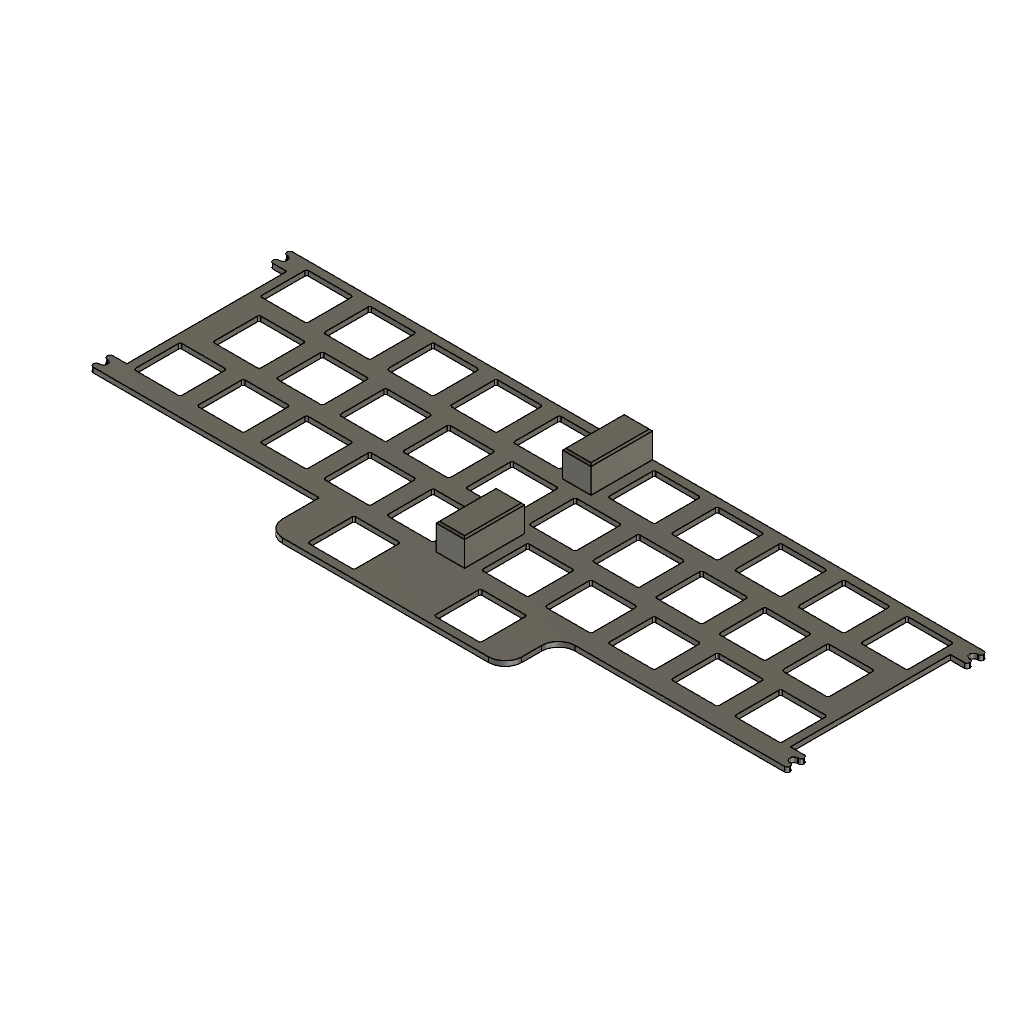
Hullstone Plate w blockers (Autodesk Fusion 360 design; units mm, degrees)
Autodesk Fusion 360 part; units mm, degrees
sketch "treadstone32platelayout" plane through (0, 0, 0) normal (0, 0, 1) x (1, 0, 0)
  line L0 (3.025, -2.525) -> (16.025, -2.525)
  line L1 (3.025, -16.525) -> (16.025, -16.525)
  line L2 (2.525, -3.025) -> (2.525, -16.025)
  line L3 (16.525, -3.025) -> (16.525, -16.025)
  arc A0 (3.025, -2.525) -> (2.525, -3.025) centre (3.025, -3.025) ccw
  arc A1 (16.525, -3.025) -> (16.025, -2.525) centre (16.025, -3.025) ccw
  arc A2 (2.525, -16.025) -> (3.025, -16.525) centre (3.025, -16.025) ccw
  arc A3 (16.025, -16.525) -> (16.525, -16.025) centre (16.025, -16.025) ccw
  line L4 (22.075, -2.525) -> (35.075, -2.525)
  line L5 (22.075, -16.525) -> (35.075, -16.525)
  line L6 (21.575, -3.025) -> (21.575, -16.025)
  line L7 (35.575, -3.025) -> (35.575, -16.025)
  arc A4 (22.075, -2.525) -> (21.575, -3.025) centre (22.075, -3.025) ccw
  arc A5 (35.575, -3.025) -> (35.075, -2.525) centre (35.075, -3.025) ccw
  arc A6 (21.575, -16.025) -> (22.075, -16.525) centre (22.075, -16.025) ccw
  arc A7 (35.075, -16.525) -> (35.575, -16.025) centre (35.075, -16.025) ccw
  line L8 (41.125, -2.525) -> (54.125, -2.525)
  line L9 (41.125, -16.525) -> (54.125, -16.525)
  line L10 (40.625, -3.025) -> (40.625, -16.025)
  line L11 (54.625, -3.025) -> (54.625, -16.025)
  arc A8 (41.125, -2.525) -> (40.625, -3.025) centre (41.125, -3.025) ccw
  arc A9 (54.625, -3.025) -> (54.125, -2.525) centre (54.125, -3.025) ccw
  arc A10 (40.625, -16.025) -> (41.125, -16.525) centre (41.125, -16.025) ccw
  arc A11 (54.125, -16.525) -> (54.625, -16.025) centre (54.125, -16.025) ccw
  line L12 (60.175, -2.525) -> (73.175, -2.525)
  line L13 (60.175, -16.525) -> (73.175, -16.525)
  line L14 (59.675, -3.025) -> (59.675, -16.025)
  line L15 (73.675, -3.025) -> (73.675, -16.025)
  arc A12 (60.175, -2.525) -> (59.675, -3.025) centre (60.175, -3.025) ccw
  arc A13 (73.675, -3.025) -> (73.175, -2.525) centre (73.175, -3.025) ccw
  arc A14 (59.675, -16.025) -> (60.175, -16.525) centre (60.175, -16.025) ccw
  arc A15 (73.175, -16.525) -> (73.675, -16.025) centre (73.175, -16.025) ccw
  line L16 (79.225, -2.525) -> (92.225, -2.525)
  line L17 (79.225, -16.525) -> (92.225, -16.525)
  line L18 (78.725, -3.025) -> (78.725, -16.025)
  line L19 (92.725, -3.025) -> (92.725, -16.025)
  arc A16 (79.225, -2.525) -> (78.725, -3.025) centre (79.225, -3.025) ccw
  arc A17 (92.725, -3.025) -> (92.225, -2.525) centre (92.225, -3.025) ccw
  arc A18 (78.725, -16.025) -> (79.225, -16.525) centre (79.225, -16.025) ccw
  arc A19 (92.225, -16.525) -> (92.725, -16.025) centre (92.225, -16.025) ccw
  line L20 (107.8, -2.525) -> (120.8, -2.525)
  line L21 (107.8, -16.525) -> (120.8, -16.525)
  line L22 (107.3, -3.025) -> (107.3, -16.025)
  line L23 (121.3, -3.025) -> (121.3, -16.025)
  arc A20 (107.8, -2.525) -> (107.3, -3.025) centre (107.8, -3.025) ccw
  arc A21 (121.3, -3.025) -> (120.8, -2.525) centre (120.8, -3.025) ccw
  arc A22 (107.3, -16.025) -> (107.8, -16.525) centre (107.8, -16.025) ccw
  arc A23 (120.8, -16.525) -> (121.3, -16.025) centre (120.8, -16.025) ccw
  line L24 (126.85, -2.525) -> (139.85, -2.525)
  line L25 (126.85, -16.525) -> (139.85, -16.525)
  line L26 (126.35, -3.025) -> (126.35, -16.025)
  line L27 (140.35, -3.025) -> (140.35, -16.025)
  arc A24 (126.85, -2.525) -> (126.35, -3.025) centre (126.85, -3.025) ccw
  arc A25 (140.35, -3.025) -> (139.85, -2.525) centre (139.85, -3.025) ccw
  arc A26 (126.35, -16.025) -> (126.85, -16.525) centre (126.85, -16.025) ccw
  arc A27 (139.85, -16.525) -> (140.35, -16.025) centre (139.85, -16.025) ccw
  line L28 (145.9, -2.525) -> (158.9, -2.525)
  line L29 (145.9, -16.525) -> (158.9, -16.525)
  line L30 (145.4, -3.025) -> (145.4, -16.025)
  line L31 (159.4, -3.025) -> (159.4, -16.025)
  arc A28 (145.9, -2.525) -> (145.4, -3.025) centre (145.9, -3.025) ccw
  arc A29 (159.4, -3.025) -> (158.9, -2.525) centre (158.9, -3.025) ccw
  arc A30 (145.4, -16.025) -> (145.9, -16.525) centre (145.9, -16.025) ccw
  arc A31 (158.9, -16.525) -> (159.4, -16.025) centre (158.9, -16.025) ccw
  line L32 (164.95, -2.525) -> (177.95, -2.525)
  line L33 (164.95, -16.525) -> (177.95, -16.525)
  line L34 (164.45, -3.025) -> (164.45, -16.025)
  line L35 (178.45, -3.025) -> (178.45, -16.025)
  arc A32 (164.95, -2.525) -> (164.45, -3.025) centre (164.95, -3.025) ccw
  arc A33 (178.45, -3.025) -> (177.95, -2.525) centre (177.95, -3.025) ccw
  arc A34 (164.45, -16.025) -> (164.95, -16.525) centre (164.95, -16.025) ccw
  arc A35 (177.95, -16.525) -> (178.45, -16.025) centre (177.95, -16.025) ccw
  line L36 (184, -2.525) -> (197, -2.525)
  line L37 (184, -16.525) -> (197, -16.525)
  line L38 (183.5, -3.025) -> (183.5, -16.025)
  line L39 (197.5, -3.025) -> (197.5, -16.025)
  arc A36 (184, -2.525) -> (183.5, -3.025) centre (184, -3.025) ccw
  arc A37 (197.5, -3.025) -> (197, -2.525) centre (197, -3.025) ccw
  arc A38 (183.5, -16.025) -> (184, -16.525) centre (184, -16.025) ccw
  arc A39 (197, -16.525) -> (197.5, -16.025) centre (197, -16.025) ccw
  line L40 (7.7875, -21.575) -> (20.7875, -21.575)
  line L41 (7.7875, -35.575) -> (20.7875, -35.575)
  line L42 (7.2875, -22.075) -> (7.2875, -35.075)
  line L43 (21.2875, -22.075) -> (21.2875, -35.075)
  arc A40 (7.7875, -21.575) -> (7.2875, -22.075) centre (7.7875, -22.075) ccw
  arc A41 (21.2875, -22.075) -> (20.7875, -21.575) centre (20.7875, -22.075) ccw
  arc A42 (7.2875, -35.075) -> (7.7875, -35.575) centre (7.7875, -35.075) ccw
  arc A43 (20.7875, -35.575) -> (21.2875, -35.075) centre (20.7875, -35.075) ccw
  line L44 (26.8375, -21.575) -> (39.8375, -21.575)
  line L45 (26.8375, -35.575) -> (39.8375, -35.575)
  line L46 (26.3375, -22.075) -> (26.3375, -35.075)
  line L47 (40.3375, -22.075) -> (40.3375, -35.075)
  arc A44 (26.8375, -21.575) -> (26.3375, -22.075) centre (26.8375, -22.075) ccw
  arc A45 (40.3375, -22.075) -> (39.8375, -21.575) centre (39.8375, -22.075) ccw
  arc A46 (26.3375, -35.075) -> (26.8375, -35.575) centre (26.8375, -35.075) ccw
  arc A47 (39.8375, -35.575) -> (40.3375, -35.075) centre (39.8375, -35.075) ccw
  line L48 (45.8875, -21.575) -> (58.8875, -21.575)
  line L49 (45.8875, -35.575) -> (58.8875, -35.575)
  line L50 (45.3875, -22.075) -> (45.3875, -35.075)
  line L51 (59.3875, -22.075) -> (59.3875, -35.075)
  arc A48 (45.8875, -21.575) -> (45.3875, -22.075) centre (45.8875, -22.075) ccw
  arc A49 (59.3875, -22.075) -> (58.8875, -21.575) centre (58.8875, -22.075) ccw
  arc A50 (45.3875, -35.075) -> (45.8875, -35.575) centre (45.8875, -35.075) ccw
  arc A51 (58.8875, -35.575) -> (59.3875, -35.075) centre (58.8875, -35.075) ccw
  line L52 (64.9375, -21.575) -> (77.9375, -21.575)
  line L53 (64.9375, -35.575) -> (77.9375, -35.575)
  line L54 (64.4375, -22.075) -> (64.4375, -35.075)
  line L55 (78.4375, -22.075) -> (78.4375, -35.075)
  arc A52 (64.9375, -21.575) -> (64.4375, -22.075) centre (64.9375, -22.075) ccw
  arc A53 (78.4375, -22.075) -> (77.9375, -21.575) centre (77.9375, -22.075) ccw
  arc A54 (64.4375, -35.075) -> (64.9375, -35.575) centre (64.9375, -35.075) ccw
  arc A55 (77.9375, -35.575) -> (78.4375, -35.075) centre (77.9375, -35.075) ccw
  line L56 (83.9875, -21.575) -> (96.9875, -21.575)
  line L57 (83.9875, -35.575) -> (96.9875, -35.575)
  line L58 (83.4875, -22.075) -> (83.4875, -35.075)
  line L59 (97.4875, -22.075) -> (97.4875, -35.075)
  arc A56 (83.9875, -21.575) -> (83.4875, -22.075) centre (83.9875, -22.075) ccw
  arc A57 (97.4875, -22.075) -> (96.9875, -21.575) centre (96.9875, -22.075) ccw
  arc A58 (83.4875, -35.075) -> (83.9875, -35.575) centre (83.9875, -35.075) ccw
  arc A59 (96.9875, -35.575) -> (97.4875, -35.075) centre (96.9875, -35.075) ccw
  line L60 (103.0375, -21.575) -> (116.0375, -21.575)
  line L61 (103.0375, -35.575) -> (116.0375, -35.575)
  line L62 (102.5375, -22.075) -> (102.5375, -35.075)
  line L63 (116.5375, -22.075) -> (116.5375, -35.075)
  arc A60 (103.0375, -21.575) -> (102.5375, -22.075) centre (103.0375, -22.075) ccw
  arc A61 (116.5375, -22.075) -> (116.0375, -21.575) centre (116.0375, -22.075) ccw
  arc A62 (102.5375, -35.075) -> (103.0375, -35.575) centre (103.0375, -35.075) ccw
  arc A63 (116.0375, -35.575) -> (116.5375, -35.075) centre (116.0375, -35.075) ccw
  line L64 (122.0875, -21.575) -> (135.0875, -21.575)
  line L65 (122.0875, -35.575) -> (135.0875, -35.575)
  line L66 (121.5875, -22.075) -> (121.5875, -35.075)
  line L67 (135.5875, -22.075) -> (135.5875, -35.075)
  arc A64 (122.0875, -21.575) -> (121.5875, -22.075) centre (122.0875, -22.075) ccw
  arc A65 (135.5875, -22.075) -> (135.0875, -21.575) centre (135.0875, -22.075) ccw
  arc A66 (121.5875, -35.075) -> (122.0875, -35.575) centre (122.0875, -35.075) ccw
  arc A67 (135.0875, -35.575) -> (135.5875, -35.075) centre (135.0875, -35.075) ccw
  line L68 (141.1375, -21.575) -> (154.1375, -21.575)
  line L69 (141.1375, -35.575) -> (154.1375, -35.575)
  line L70 (140.6375, -22.075) -> (140.6375, -35.075)
  line L71 (154.6375, -22.075) -> (154.6375, -35.075)
  arc A68 (141.1375, -21.575) -> (140.6375, -22.075) centre (141.1375, -22.075) ccw
  arc A69 (154.6375, -22.075) -> (154.1375, -21.575) centre (154.1375, -22.075) ccw
  arc A70 (140.6375, -35.075) -> (141.1375, -35.575) centre (141.1375, -35.075) ccw
  arc A71 (154.1375, -35.575) -> (154.6375, -35.075) centre (154.1375, -35.075) ccw
  line L72 (160.1875, -21.575) -> (173.1875, -21.575)
  line L73 (160.1875, -35.575) -> (173.1875, -35.575)
  line L74 (159.6875, -22.075) -> (159.6875, -35.075)
  line L75 (173.6875, -22.075) -> (173.6875, -35.075)
  arc A72 (160.1875, -21.575) -> (159.6875, -22.075) centre (160.1875, -22.075) ccw
  arc A73 (173.6875, -22.075) -> (173.1875, -21.575) centre (173.1875, -22.075) ccw
  arc A74 (159.6875, -35.075) -> (160.1875, -35.575) centre (160.1875, -35.075) ccw
  arc A75 (173.1875, -35.575) -> (173.6875, -35.075) centre (173.1875, -35.075) ccw
  line L76 (179.2375, -21.575) -> (192.2375, -21.575)
  line L77 (179.2375, -35.575) -> (192.2375, -35.575)
  line L78 (178.7375, -22.075) -> (178.7375, -35.075)
  line L79 (192.7375, -22.075) -> (192.7375, -35.075)
  arc A76 (179.2375, -21.575) -> (178.7375, -22.075) centre (179.2375, -22.075) ccw
  arc A77 (192.7375, -22.075) -> (192.2375, -21.575) centre (192.2375, -22.075) ccw
  arc A78 (178.7375, -35.075) -> (179.2375, -35.575) centre (179.2375, -35.075) ccw
  arc A79 (192.2375, -35.575) -> (192.7375, -35.075) centre (192.2375, -35.075) ccw
  line L80 (3.025, -40.625) -> (16.025, -40.625)
  line L81 (3.025, -54.625) -> (16.025, -54.625)
  line L82 (2.525, -41.125) -> (2.525, -54.125)
  line L83 (16.525, -41.125) -> (16.525, -54.125)
  arc A80 (3.025, -40.625) -> (2.525, -41.125) centre (3.025, -41.125) ccw
  arc A81 (16.525, -41.125) -> (16.025, -40.625) centre (16.025, -41.125) ccw
  arc A82 (2.525, -54.125) -> (3.025, -54.625) centre (3.025, -54.125) ccw
  arc A83 (16.025, -54.625) -> (16.525, -54.125) centre (16.025, -54.125) ccw
  line L84 (22.075, -40.625) -> (35.075, -40.625)
  line L85 (22.075, -54.625) -> (35.075, -54.625)
  line L86 (21.575, -41.125) -> (21.575, -54.125)
  line L87 (35.575, -41.125) -> (35.575, -54.125)
  arc A84 (22.075, -40.625) -> (21.575, -41.125) centre (22.075, -41.125) ccw
  arc A85 (35.575, -41.125) -> (35.075, -40.625) centre (35.075, -41.125) ccw
  arc A86 (21.575, -54.125) -> (22.075, -54.625) centre (22.075, -54.125) ccw
  arc A87 (35.075, -54.625) -> (35.575, -54.125) centre (35.075, -54.125) ccw
  line L88 (41.125, -40.625) -> (54.125, -40.625)
  line L89 (41.125, -54.625) -> (54.125, -54.625)
  line L90 (40.625, -41.125) -> (40.625, -54.125)
  line L91 (54.625, -41.125) -> (54.625, -54.125)
  arc A88 (41.125, -40.625) -> (40.625, -41.125) centre (41.125, -41.125) ccw
  arc A89 (54.625, -41.125) -> (54.125, -40.625) centre (54.125, -41.125) ccw
  arc A90 (40.625, -54.125) -> (41.125, -54.625) centre (41.125, -54.125) ccw
  arc A91 (54.125, -54.625) -> (54.625, -54.125) centre (54.125, -54.125) ccw
  line L92 (60.175, -40.625) -> (73.175, -40.625)
  line L93 (60.175, -54.625) -> (73.175, -54.625)
  line L94 (59.675, -41.125) -> (59.675, -54.125)
  line L95 (73.675, -41.125) -> (73.675, -54.125)
  arc A92 (60.175, -40.625) -> (59.675, -41.125) centre (60.175, -41.125) ccw
  arc A93 (73.675, -41.125) -> (73.175, -40.625) centre (73.175, -41.125) ccw
  arc A94 (59.675, -54.125) -> (60.175, -54.625) centre (60.175, -54.125) ccw
  arc A95 (73.175, -54.625) -> (73.675, -54.125) centre (73.175, -54.125) ccw
  line L96 (79.225, -40.625) -> (92.225, -40.625)
  line L97 (79.225, -54.625) -> (92.225, -54.625)
  line L98 (78.725, -41.125) -> (78.725, -54.125)
  line L99 (92.725, -41.125) -> (92.725, -54.125)
  arc A96 (79.225, -40.625) -> (78.725, -41.125) centre (79.225, -41.125) ccw
  arc A97 (92.725, -41.125) -> (92.225, -40.625) centre (92.225, -41.125) ccw
  arc A98 (78.725, -54.125) -> (79.225, -54.625) centre (79.225, -54.125) ccw
  arc A99 (92.225, -54.625) -> (92.725, -54.125) centre (92.225, -54.125) ccw
  line L100 (107.8, -40.625) -> (120.8, -40.625)
  line L101 (107.8, -54.625) -> (120.8, -54.625)
  line L102 (107.3, -41.125) -> (107.3, -54.125)
  line L103 (121.3, -41.125) -> (121.3, -54.125)
  arc A100 (107.8, -40.625) -> (107.3, -41.125) centre (107.8, -41.125) ccw
  arc A101 (121.3, -41.125) -> (120.8, -40.625) centre (120.8, -41.125) ccw
  arc A102 (107.3, -54.125) -> (107.8, -54.625) centre (107.8, -54.125) ccw
  arc A103 (120.8, -54.625) -> (121.3, -54.125) centre (120.8, -54.125) ccw
  line L104 (126.85, -40.625) -> (139.85, -40.625)
  line L105 (126.85, -54.625) -> (139.85, -54.625)
  line L106 (126.35, -41.125) -> (126.35, -54.125)
  line L107 (140.35, -41.125) -> (140.35, -54.125)
  arc A104 (126.85, -40.625) -> (126.35, -41.125) centre (126.85, -41.125) ccw
  arc A105 (140.35, -41.125) -> (139.85, -40.625) centre (139.85, -41.125) ccw
  arc A106 (126.35, -54.125) -> (126.85, -54.625) centre (126.85, -54.125) ccw
  arc A107 (139.85, -54.625) -> (140.35, -54.125) centre (139.85, -54.125) ccw
  line L108 (145.9, -40.625) -> (158.9, -40.625)
  line L109 (145.9, -54.625) -> (158.9, -54.625)
  line L110 (145.4, -41.125) -> (145.4, -54.125)
  line L111 (159.4, -41.125) -> (159.4, -54.125)
  arc A108 (145.9, -40.625) -> (145.4, -41.125) centre (145.9, -41.125) ccw
  arc A109 (159.4, -41.125) -> (158.9, -40.625) centre (158.9, -41.125) ccw
  arc A110 (145.4, -54.125) -> (145.9, -54.625) centre (145.9, -54.125) ccw
  arc A111 (158.9, -54.625) -> (159.4, -54.125) centre (158.9, -54.125) ccw
  line L112 (164.95, -40.625) -> (177.95, -40.625)
  line L113 (164.95, -54.625) -> (177.95, -54.625)
  line L114 (164.45, -41.125) -> (164.45, -54.125)
  line L115 (178.45, -41.125) -> (178.45, -54.125)
  arc A112 (164.95, -40.625) -> (164.45, -41.125) centre (164.95, -41.125) ccw
  arc A113 (178.45, -41.125) -> (177.95, -40.625) centre (177.95, -41.125) ccw
  arc A114 (164.45, -54.125) -> (164.95, -54.625) centre (164.95, -54.125) ccw
  arc A115 (177.95, -54.625) -> (178.45, -54.125) centre (177.95, -54.125) ccw
  line L116 (184, -40.625) -> (197, -40.625)
  line L117 (184, -54.625) -> (197, -54.625)
  line L118 (183.5, -41.125) -> (183.5, -54.125)
  line L119 (197.5, -41.125) -> (197.5, -54.125)
  arc A116 (184, -40.625) -> (183.5, -41.125) centre (184, -41.125) ccw
  arc A117 (197.5, -41.125) -> (197, -40.625) centre (197, -41.125) ccw
  arc A118 (183.5, -54.125) -> (184, -54.625) centre (184, -54.125) ccw
  arc A119 (197, -54.625) -> (197.5, -54.125) centre (197, -54.125) ccw
  line L120 (74.4625, -59.675) -> (87.4625, -59.675)
  line L121 (74.4625, -73.675) -> (87.4625, -73.675)
  line L122 (73.9625, -60.1812) -> (73.9625, -73.175)
  line L123 (87.9625, -60.175) -> (87.9625, -73.175)
  arc A120 (74.4625, -59.675) -> (73.9625, -60.1812) centre (74.4625, -60.175) ccw
  arc A121 (87.9625, -60.175) -> (87.4625, -59.675) centre (87.4625, -60.175) ccw
  arc A122 (73.9625, -73.175) -> (74.4625, -73.675) centre (74.4625, -73.175) ccw
  arc A123 (87.4625, -73.675) -> (87.9625, -73.175) centre (87.4625, -73.175) ccw
  line L124 (112.5625, -59.675) -> (125.5625, -59.675)
  line L125 (112.5625, -73.675) -> (125.5625, -73.675)
  line L126 (112.0625, -60.175) -> (112.0625, -73.175)
  line L127 (126.0625, -60.1812) -> (126.0625, -73.175)
  arc A124 (112.5625, -59.675) -> (112.0625, -60.175) centre (112.5625, -60.175) ccw
  arc A125 (126.0625, -60.1812) -> (125.5625, -59.675) centre (125.5625, -60.175) ccw
  arc A126 (112.0625, -73.175) -> (112.5625, -73.675) centre (112.5625, -73.175) ccw
  arc A127 (125.5625, -73.675) -> (126.0625, -73.175) centre (125.5625, -73.175) ccw
  line L128 (68.9625, -76.2) -> (131.0625, -76.2)
  line L129 (0, 0) -> (200.025, 0)
  line L130 (0, -60.1812) -> (0, 0)
  line L131 (200.025, -60.1812) -> (200.025, 0)
  line L132 (136.0625, -65.1812) -> (136.0625, -71.2)
  line L133 (63.9625, -60.1812) -> (63.9625, -71.2)
  line L134 (200.025, -60.1812) -> (141.0625, -60.1812)
  line L135 (63.9625, -60.1812) -> (0, -60.1812)
  arc A128 (63.9625, -71.2) -> (68.9625, -76.2) centre (68.9625, -71.2) ccw
  arc A129 (131.0625, -76.2) -> (136.0625, -71.2) centre (131.0625, -71.2) ccw
  arc A130 (141.0625, -60.1812) -> (136.0625, -65.1812) centre (141.0625, -65.1812) ccw
  line L136 (200.025, -60.1812) -> (204.225, -60.1812)
  line L137 (204.225, -54.1812) -> (200.025, -54.1812)
  line L138 (200.025, -54.1812) -> (200.025, -60.1812)
  line L139 (200.025, 0) -> (204.225, 0)
  line L140 (204.225, -6) -> (200.025, -6)
  line L141 (200.025, -6) -> (200.025, 0)
  line L142 (0, 0) -> (-4.2, 0)
  line L143 (-4.2, -6) -> (0, -6)
  line L144 (0, -6) -> (0, 0)
  line L145 (0, -60.1812) -> (-4.2, -60.1812)
  line L146 (-4.2, -54.1812) -> (0, -54.1812)
  line L147 (0, -54.1812) -> (0, -60.1812)
  line L148 (-4.0098, -55.9812) -> (-4.2, -55.9812)
  line L149 (-4.0075, -58.3812) -> (-4.2, -58.3812)
  arc A131 (-4.012, -58.3812) -> (-4.0098, -55.9812) centre (-4.0098, -57.1812) ccw
  line L150 (-5, -59.3812) -> (-5, -59.1812)
  line L151 (-5, -55.1812) -> (-5, -54.9812)
  line L152 (204.025, -55.975) -> (204.225, -55.975)
  line L153 (204.025, -58.375) -> (204.225, -58.375)
  arc A132 (204.025, -55.975) -> (204.025, -58.375) centre (204.025, -57.175) ccw
  line L154 (205.025, -59.3812) -> (205.025, -59.175)
  line L155 (205.025, -55.175) -> (205.025, -54.9812)
  line L156 (205.025, -0.8) -> (205.025, -1)
  line L157 (205.025, -5) -> (205.025, -5.2)
  arc A133 (204.025, -1.8) -> (204.0255, -4.2) centre (204.025, -3) ccw
  line L158 (204.0245, -4.2) -> (204.225, -4.2)
  line L159 (204.025, -1.8) -> (204.225, -1.8)
  line L160 (-4, -1.8) -> (-4.2, -1.8)
  line L161 (-3.9994, -4.2) -> (-4.2, -4.2)
  line L162 (-5, -0.8) -> (-5, -1)
  line L163 (-5, -5) -> (-5, -5.2)
  arc A134 (-4.0006, -4.2) -> (-4, -1.8) centre (-4, -3) ccw
  arc A135 (-5, -1) -> (-4.2, -1.8) centre (-4.2, -1) ccw
  arc A136 (-4.2, 0) -> (-5, -0.8) centre (-4.2, -0.8) ccw
  arc A137 (-4.2, -4.2) -> (-5, -5) centre (-4.2, -5) ccw
  arc A138 (-5, -5.2) -> (-4.2, -6) centre (-4.2, -5.2) ccw
  arc A139 (-4.2, -54.1812) -> (-5, -54.9812) centre (-4.2, -54.9812) ccw
  arc A140 (-5, -55.1812) -> (-4.2, -55.9812) centre (-4.2, -55.1812) ccw
  arc A141 (-4.2, -58.3812) -> (-5, -59.1812) centre (-4.2, -59.1812) ccw
  arc A142 (-5, -59.3812) -> (-4.2, -60.1812) centre (-4.2, -59.3812) ccw
  arc A143 (205.025, -59.175) -> (204.225, -58.375) centre (204.225, -59.175) ccw
  arc A144 (204.225, -60.1812) -> (205.025, -59.3812) centre (204.225, -59.3812) ccw
  arc A145 (204.225, -55.975) -> (205.025, -55.175) centre (204.225, -55.175) ccw
  arc A146 (205.025, -54.9812) -> (204.225, -54.1812) centre (204.225, -54.9812) ccw
  arc A147 (204.225, -6) -> (205.025, -5.2) centre (204.225, -5.2) ccw
  arc A148 (205.025, -5) -> (204.225, -4.2) centre (204.225, -5) ccw
  arc A149 (204.225, -1.8) -> (205.025, -1) centre (204.225, -1) ccw
  arc A150 (205.025, -0.8) -> (204.225, 0) centre (204.225, -0.8) ccw
  point P0 (136.0625, -60.1812)
  point P1 (205.025, -60.1812)
  point P2 (205.025, 0)
  point P3 (-5, 0)
  dimension "d1" = 10
  dimension "d2" = 10
  dimension "d3" = 5
  dimension "d4" = 5
  dimension "d5" = 6
  dimension "d8" = 5
  dimension "d9" = 6
  dimension "d10" = 2.4
  dimension "d11" = 2.4
  dimension "d13" = 2.4
  dimension "d15" = 2.4
  dimension "d16" = 0.8
  dimension "d19" = 3
  constraint perpendicular L130 L134
  constraint perpendicular L128 L132
  constraint perpendicular L128 L133
  constraint collinear L134 L135
  constraint tangent L133 A128
  constraint tangent L128 A128
  constraint tangent L128 A129
  constraint tangent L132 A129
  constraint equal A128 A129
  constraint coincident P0 L134
  constraint coincident P0 L132
  constraint tangent L134 A130
  constraint tangent L132 A130
  constraint equal A128 A130
  constraint horizontal L136
  constraint vertical L154
  constraint horizontal L137
  constraint vertical L138
  constraint horizontal L139
  constraint vertical L156
  constraint horizontal L140
  constraint vertical L141
  constraint horizontal L142
  constraint vertical L162
  constraint horizontal L143
  constraint vertical L144
  constraint horizontal L145
  constraint vertical L150
  constraint horizontal L146
  constraint vertical L147
  constraint perpendicular L148 L150
  constraint perpendicular L149 L150
  constraint coincident L149 A131.start
  constraint collinear L150 L151
  constraint coincident A131 L149.start
  constraint tangent L152 A132
  constraint tangent L153 A132
  constraint collinear L154 L155
  constraint collinear L156 L157
  constraint coincident A133 L158.start
  constraint coincident L158 A133.end
  constraint horizontal L160
  constraint collinear L162 L163
  constraint coincident L161 A134.start
  constraint coincident A134 L161.start
  constraint tangent L160 A135
  constraint tangent L162 A135
  constraint coincident P3 L162
  constraint coincident P3 L142
  constraint tangent L162 A136
  constraint tangent L142 A136
  constraint equal A135 A136
  constraint tangent L161 A137
  constraint tangent L163 A137
  constraint equal A135 A137
  constraint tangent L163 A138
  constraint tangent L143 A138
  constraint equal A135 A138
  constraint tangent L146 A139
  constraint tangent L151 A139
  constraint equal A135 A139
  constraint tangent L151 A140
  constraint tangent L148 A140
  constraint equal A135 A140
  constraint tangent L149 A141
  constraint tangent L150 A141
  constraint equal A135 A141
  constraint tangent L150 A142
  constraint tangent L145 A142
  constraint equal A135 A142
  constraint tangent L153 A143
  constraint tangent L154 A143
  constraint equal A135 A143
  constraint coincident P1 L154
  constraint coincident P1 L136
  constraint tangent L154 A144
  constraint tangent L136 A144
  constraint equal A135 A144
  constraint tangent L152 A145
  constraint tangent L155 A145
  constraint equal A135 A145
  constraint tangent L155 A146
  constraint tangent L137 A146
  constraint equal A135 A146
  constraint tangent L140 A147
  constraint tangent L157 A147
  constraint equal A135 A147
  constraint tangent L157 A148
  constraint tangent L158 A148
  constraint equal A135 A148
  constraint tangent L159 A149
  constraint tangent L156 A149
  constraint equal A135 A149
  constraint coincident P2 L139
  constraint coincident P2 L156
  constraint tangent L139 A150
  constraint tangent L156 A150
  constraint equal A135 A150
  measures "d1" distance of L127.start P0
  measures "d2" distance of L122.start L133.start
  measures "d3" radius of A128
  measures "d4" distance of L131.start P1
  measures "d5" distance of L131.start L137.end
  measures "d8" distance of L129.start P3
  measures "d9" distance of L130.start L146.end
  measures "d10" diameter of A131
  measures "d11" diameter of A134
  measures "d13" diameter of A133
  measures "d15" diameter of A132
  measures "d16" radius of A135
  measures "d19" distance of L146 A131.centre
extrude "Extrude1" add sketch "treadstone32platelayout" along normal blind 1.5
sketch "Sketch2" plane through (0, 0, 1.5) normal (0, 0, 1) x (-1, 0, 0)
  arc A0 (-164.95, 40.625) -> (-164.45, 41.125) centre (-164.95, 41.125) ccw
  line L0 (-164.95, 40.625) -> (-177.95, 40.625)
  arc A1 (-178.45, 41.125) -> (-177.95, 40.625) centre (-177.95, 41.125) ccw
  line L1 (-178.45, 41.125) -> (-178.45, 54.125)
  arc A2 (-177.95, 54.625) -> (-178.45, 54.125) centre (-177.95, 54.125) ccw
  line L2 (-177.95, 54.625) -> (-164.95, 54.625)
  arc A3 (-164.45, 54.125) -> (-164.95, 54.625) centre (-164.95, 54.125) ccw
  line L3 (-164.45, 54.125) -> (-164.45, 41.125)
  arc A4 (-184, 40.625) -> (-183.5, 41.125) centre (-184, 41.125) ccw
  line L4 (-184, 40.625) -> (-197, 40.625)
  arc A5 (-197.5, 41.125) -> (-197, 40.625) centre (-197, 41.125) ccw
  line L5 (-197.5, 41.125) -> (-197.5, 54.125)
  arc A6 (-197, 54.625) -> (-197.5, 54.125) centre (-197, 54.125) ccw
  line L6 (-197, 54.625) -> (-184, 54.625)
  arc A7 (-183.5, 54.125) -> (-184, 54.625) centre (-184, 54.125) ccw
  line L7 (-183.5, 54.125) -> (-183.5, 41.125)
  arc A8 (-74.4625, 59.675) -> (-73.9625, 60.1812) centre (-74.4625, 60.175) ccw
  line L8 (-74.4625, 59.675) -> (-87.4625, 59.675)
  arc A9 (-87.9625, 60.175) -> (-87.4625, 59.675) centre (-87.4625, 60.175) ccw
  line L9 (-87.9625, 60.175) -> (-87.9625, 73.175)
  arc A10 (-87.4625, 73.675) -> (-87.9625, 73.175) centre (-87.4625, 73.175) ccw
  line L10 (-87.4625, 73.675) -> (-74.4625, 73.675)
  arc A11 (-73.9625, 73.175) -> (-74.4625, 73.675) centre (-74.4625, 73.175) ccw
  line L11 (-73.9625, 73.175) -> (-73.9625, 60.1812)
  arc A12 (-145.9, 40.625) -> (-145.4, 41.125) centre (-145.9, 41.125) ccw
  line L12 (-145.9, 40.625) -> (-158.9, 40.625)
  arc A13 (-159.4, 41.125) -> (-158.9, 40.625) centre (-158.9, 41.125) ccw
  line L13 (-159.4, 41.125) -> (-159.4, 54.125)
  arc A14 (-158.9, 54.625) -> (-159.4, 54.125) centre (-158.9, 54.125) ccw
  line L14 (-158.9, 54.625) -> (-145.9, 54.625)
  arc A15 (-145.4, 54.125) -> (-145.9, 54.625) centre (-145.9, 54.125) ccw
  line L15 (-145.4, 54.125) -> (-145.4, 41.125)
  arc A16 (-26.8375, 21.575) -> (-26.3375, 22.075) centre (-26.8375, 22.075) ccw
  line L16 (-26.8375, 21.575) -> (-39.8375, 21.575)
  arc A17 (-40.3375, 22.075) -> (-39.8375, 21.575) centre (-39.8375, 22.075) ccw
  line L17 (-40.3375, 22.075) -> (-40.3375, 35.075)
  arc A18 (-39.8375, 35.575) -> (-40.3375, 35.075) centre (-39.8375, 35.075) ccw
  line L18 (-39.8375, 35.575) -> (-26.8375, 35.575)
  arc A19 (-26.3375, 35.075) -> (-26.8375, 35.575) centre (-26.8375, 35.075) ccw
  line L19 (-26.3375, 35.075) -> (-26.3375, 22.075)
  arc A20 (-45.8875, 21.575) -> (-45.3875, 22.075) centre (-45.8875, 22.075) ccw
  line L20 (-45.8875, 21.575) -> (-58.8875, 21.575)
  arc A21 (-59.3875, 22.075) -> (-58.8875, 21.575) centre (-58.8875, 22.075) ccw
  line L21 (-59.3875, 22.075) -> (-59.3875, 35.075)
  arc A22 (-58.8875, 35.575) -> (-59.3875, 35.075) centre (-58.8875, 35.075) ccw
  line L22 (-58.8875, 35.575) -> (-45.8875, 35.575)
  arc A23 (-45.3875, 35.075) -> (-45.8875, 35.575) centre (-45.8875, 35.075) ccw
  line L23 (-45.3875, 35.075) -> (-45.3875, 22.075)
  arc A24 (-126.85, 40.625) -> (-126.35, 41.125) centre (-126.85, 41.125) ccw
  line L24 (-126.85, 40.625) -> (-139.85, 40.625)
  arc A25 (-140.35, 41.125) -> (-139.85, 40.625) centre (-139.85, 41.125) ccw
  line L25 (-140.35, 41.125) -> (-140.35, 54.125)
  arc A26 (-139.85, 54.625) -> (-140.35, 54.125) centre (-139.85, 54.125) ccw
  line L26 (-139.85, 54.625) -> (-126.85, 54.625)
  arc A27 (-126.35, 54.125) -> (-126.85, 54.625) centre (-126.85, 54.125) ccw
  line L27 (-126.35, 54.125) -> (-126.35, 41.125)
  arc A28 (-107.8, 40.625) -> (-107.3, 41.125) centre (-107.8, 41.125) ccw
  line L28 (-107.8, 40.625) -> (-120.8, 40.625)
  arc A29 (-121.3, 41.125) -> (-120.8, 40.625) centre (-120.8, 41.125) ccw
  line L29 (-121.3, 41.125) -> (-121.3, 54.125)
  arc A30 (-120.8, 54.625) -> (-121.3, 54.125) centre (-120.8, 54.125) ccw
  line L30 (-120.8, 54.625) -> (-107.8, 54.625)
  arc A31 (-107.3, 54.125) -> (-107.8, 54.625) centre (-107.8, 54.125) ccw
  line L31 (-107.3, 54.125) -> (-107.3, 41.125)
  arc A32 (-112.5625, 59.675) -> (-112.0625, 60.175) centre (-112.5625, 60.175) ccw
  line L32 (-112.5625, 59.675) -> (-125.5625, 59.675)
  arc A33 (-126.0625, 60.1812) -> (-125.5625, 59.675) centre (-125.5625, 60.175) ccw
  line L33 (-126.0625, 60.1812) -> (-126.0625, 73.175)
  arc A34 (-125.5625, 73.675) -> (-126.0625, 73.175) centre (-125.5625, 73.175) ccw
  line L34 (-125.5625, 73.675) -> (-112.5625, 73.675)
  arc A35 (-112.0625, 73.175) -> (-112.5625, 73.675) centre (-112.5625, 73.175) ccw
  line L35 (-112.0625, 73.175) -> (-112.0625, 60.175)
  arc A36 (-79.225, 40.625) -> (-78.725, 41.125) centre (-79.225, 41.125) ccw
  line L36 (-79.225, 40.625) -> (-92.225, 40.625)
  arc A37 (-92.725, 41.125) -> (-92.225, 40.625) centre (-92.225, 41.125) ccw
  line L37 (-92.725, 41.125) -> (-92.725, 54.125)
  arc A38 (-92.225, 54.625) -> (-92.725, 54.125) centre (-92.225, 54.125) ccw
  line L38 (-92.225, 54.625) -> (-79.225, 54.625)
  arc A39 (-78.725, 54.125) -> (-79.225, 54.625) centre (-79.225, 54.125) ccw
  line L39 (-78.725, 54.125) -> (-78.725, 41.125)
  arc A40 (-60.175, 40.625) -> (-59.675, 41.125) centre (-60.175, 41.125) ccw
  line L40 (-60.175, 40.625) -> (-73.175, 40.625)
  arc A41 (-73.675, 41.125) -> (-73.175, 40.625) centre (-73.175, 41.125) ccw
  line L41 (-73.675, 41.125) -> (-73.675, 54.125)
  arc A42 (-73.175, 54.625) -> (-73.675, 54.125) centre (-73.175, 54.125) ccw
  line L42 (-73.175, 54.625) -> (-60.175, 54.625)
  arc A43 (-59.675, 54.125) -> (-60.175, 54.625) centre (-60.175, 54.125) ccw
  line L43 (-59.675, 54.125) -> (-59.675, 41.125)
  arc A44 (-41.125, 40.625) -> (-40.625, 41.125) centre (-41.125, 41.125) ccw
  line L44 (-41.125, 40.625) -> (-54.125, 40.625)
  arc A45 (-54.625, 41.125) -> (-54.125, 40.625) centre (-54.125, 41.125) ccw
  line L45 (-54.625, 41.125) -> (-54.625, 54.125)
  arc A46 (-54.125, 54.625) -> (-54.625, 54.125) centre (-54.125, 54.125) ccw
  line L46 (-54.125, 54.625) -> (-41.125, 54.625)
  arc A47 (-40.625, 54.125) -> (-41.125, 54.625) centre (-41.125, 54.125) ccw
  line L47 (-40.625, 54.125) -> (-40.625, 41.125)
  arc A48 (-22.075, 40.625) -> (-21.575, 41.125) centre (-22.075, 41.125) ccw
  line L48 (-22.075, 40.625) -> (-35.075, 40.625)
  arc A49 (-35.575, 41.125) -> (-35.075, 40.625) centre (-35.075, 41.125) ccw
  line L49 (-35.575, 41.125) -> (-35.575, 54.125)
  arc A50 (-35.075, 54.625) -> (-35.575, 54.125) centre (-35.075, 54.125) ccw
  line L50 (-35.075, 54.625) -> (-22.075, 54.625)
  arc A51 (-21.575, 54.125) -> (-22.075, 54.625) centre (-22.075, 54.125) ccw
  line L51 (-21.575, 54.125) -> (-21.575, 41.125)
  arc A52 (-3.025, 40.625) -> (-2.525, 41.125) centre (-3.025, 41.125) ccw
  line L52 (-3.025, 40.625) -> (-16.025, 40.625)
  arc A53 (-16.525, 41.125) -> (-16.025, 40.625) centre (-16.025, 41.125) ccw
  line L53 (-16.525, 41.125) -> (-16.525, 54.125)
  arc A54 (-16.025, 54.625) -> (-16.525, 54.125) centre (-16.025, 54.125) ccw
  line L54 (-16.025, 54.625) -> (-3.025, 54.625)
  arc A55 (-2.525, 54.125) -> (-3.025, 54.625) centre (-3.025, 54.125) ccw
  line L55 (-2.525, 54.125) -> (-2.525, 41.125)
  arc A56 (-179.2375, 21.575) -> (-178.7375, 22.075) centre (-179.2375, 22.075) ccw
  line L56 (-179.2375, 21.575) -> (-192.2375, 21.575)
  arc A57 (-192.7375, 22.075) -> (-192.2375, 21.575) centre (-192.2375, 22.075) ccw
  line L57 (-192.7375, 22.075) -> (-192.7375, 35.075)
  arc A58 (-192.2375, 35.575) -> (-192.7375, 35.075) centre (-192.2375, 35.075) ccw
  line L58 (-192.2375, 35.575) -> (-179.2375, 35.575)
  arc A59 (-178.7375, 35.075) -> (-179.2375, 35.575) centre (-179.2375, 35.075) ccw
  line L59 (-178.7375, 35.075) -> (-178.7375, 22.075)
  arc A60 (-160.1875, 21.575) -> (-159.6875, 22.075) centre (-160.1875, 22.075) ccw
  line L60 (-160.1875, 21.575) -> (-173.1875, 21.575)
  arc A61 (-173.6875, 22.075) -> (-173.1875, 21.575) centre (-173.1875, 22.075) ccw
  line L61 (-173.6875, 22.075) -> (-173.6875, 35.075)
  arc A62 (-173.1875, 35.575) -> (-173.6875, 35.075) centre (-173.1875, 35.075) ccw
  line L62 (-173.1875, 35.575) -> (-160.1875, 35.575)
  arc A63 (-159.6875, 35.075) -> (-160.1875, 35.575) centre (-160.1875, 35.075) ccw
  line L63 (-159.6875, 35.075) -> (-159.6875, 22.075)
  arc A64 (-141.1375, 21.575) -> (-140.6375, 22.075) centre (-141.1375, 22.075) ccw
  line L64 (-141.1375, 21.575) -> (-154.1375, 21.575)
  arc A65 (-154.6375, 22.075) -> (-154.1375, 21.575) centre (-154.1375, 22.075) ccw
  line L65 (-154.6375, 22.075) -> (-154.6375, 35.075)
  arc A66 (-154.1375, 35.575) -> (-154.6375, 35.075) centre (-154.1375, 35.075) ccw
  line L66 (-154.1375, 35.575) -> (-141.1375, 35.575)
  arc A67 (-140.6375, 35.075) -> (-141.1375, 35.575) centre (-141.1375, 35.075) ccw
  line L67 (-140.6375, 35.075) -> (-140.6375, 22.075)
  arc A68 (-122.0875, 21.575) -> (-121.5875, 22.075) centre (-122.0875, 22.075) ccw
  line L68 (-122.0875, 21.575) -> (-135.0875, 21.575)
  arc A69 (-135.5875, 22.075) -> (-135.0875, 21.575) centre (-135.0875, 22.075) ccw
  line L69 (-135.5875, 22.075) -> (-135.5875, 35.075)
  arc A70 (-135.0875, 35.575) -> (-135.5875, 35.075) centre (-135.0875, 35.075) ccw
  line L70 (-135.0875, 35.575) -> (-122.0875, 35.575)
  arc A71 (-121.5875, 35.075) -> (-122.0875, 35.575) centre (-122.0875, 35.075) ccw
  line L71 (-121.5875, 35.075) -> (-121.5875, 22.075)
  arc A72 (-103.0375, 21.575) -> (-102.5375, 22.075) centre (-103.0375, 22.075) ccw
  line L72 (-103.0375, 21.575) -> (-116.0375, 21.575)
  arc A73 (-116.5375, 22.075) -> (-116.0375, 21.575) centre (-116.0375, 22.075) ccw
  line L73 (-116.5375, 22.075) -> (-116.5375, 35.075)
  arc A74 (-116.0375, 35.575) -> (-116.5375, 35.075) centre (-116.0375, 35.075) ccw
  line L74 (-116.0375, 35.575) -> (-103.0375, 35.575)
  arc A75 (-102.5375, 35.075) -> (-103.0375, 35.575) centre (-103.0375, 35.075) ccw
  line L75 (-102.5375, 35.075) -> (-102.5375, 22.075)
  arc A76 (-83.9875, 21.575) -> (-83.4875, 22.075) centre (-83.9875, 22.075) ccw
  line L76 (-83.9875, 21.575) -> (-96.9875, 21.575)
  arc A77 (-97.4875, 22.075) -> (-96.9875, 21.575) centre (-96.9875, 22.075) ccw
  line L77 (-97.4875, 22.075) -> (-97.4875, 35.075)
  arc A78 (-96.9875, 35.575) -> (-97.4875, 35.075) centre (-96.9875, 35.075) ccw
  line L78 (-96.9875, 35.575) -> (-83.9875, 35.575)
  arc A79 (-83.4875, 35.075) -> (-83.9875, 35.575) centre (-83.9875, 35.075) ccw
  line L79 (-83.4875, 35.075) -> (-83.4875, 22.075)
  arc A80 (-64.9375, 21.575) -> (-64.4375, 22.075) centre (-64.9375, 22.075) ccw
  line L80 (-64.9375, 21.575) -> (-77.9375, 21.575)
  arc A81 (-78.4375, 22.075) -> (-77.9375, 21.575) centre (-77.9375, 22.075) ccw
  line L81 (-78.4375, 22.075) -> (-78.4375, 35.075)
  arc A82 (-77.9375, 35.575) -> (-78.4375, 35.075) centre (-77.9375, 35.075) ccw
  line L82 (-77.9375, 35.575) -> (-64.9375, 35.575)
  arc A83 (-64.4375, 35.075) -> (-64.9375, 35.575) centre (-64.9375, 35.075) ccw
  line L83 (-64.4375, 35.075) -> (-64.4375, 22.075)
  arc A84 (-145.9, 2.525) -> (-145.4, 3.025) centre (-145.9, 3.025) ccw
  line L84 (-145.9, 2.525) -> (-158.9, 2.525)
  arc A85 (-159.4, 3.025) -> (-158.9, 2.525) centre (-158.9, 3.025) ccw
  line L85 (-159.4, 3.025) -> (-159.4, 16.025)
  arc A86 (-158.9, 16.525) -> (-159.4, 16.025) centre (-158.9, 16.025) ccw
  line L86 (-158.9, 16.525) -> (-145.9, 16.525)
  arc A87 (-145.4, 16.025) -> (-145.9, 16.525) centre (-145.9, 16.025) ccw
  line L87 (-145.4, 16.025) -> (-145.4, 3.025)
  arc A88 (-164.95, 2.525) -> (-164.45, 3.025) centre (-164.95, 3.025) ccw
  line L88 (-164.95, 2.525) -> (-177.95, 2.525)
  arc A89 (-178.45, 3.025) -> (-177.95, 2.525) centre (-177.95, 3.025) ccw
  line L89 (-178.45, 3.025) -> (-178.45, 16.025)
  arc A90 (-177.95, 16.525) -> (-178.45, 16.025) centre (-177.95, 16.025) ccw
  line L90 (-177.95, 16.525) -> (-164.95, 16.525)
  arc A91 (-164.45, 16.025) -> (-164.95, 16.525) centre (-164.95, 16.025) ccw
  line L91 (-164.45, 16.025) -> (-164.45, 3.025)
  arc A92 (-184, 2.525) -> (-183.5, 3.025) centre (-184, 3.025) ccw
  line L92 (-184, 2.525) -> (-197, 2.525)
  arc A93 (-197.5, 3.025) -> (-197, 2.525) centre (-197, 3.025) ccw
  line L93 (-197.5, 3.025) -> (-197.5, 16.025)
  arc A94 (-197, 16.525) -> (-197.5, 16.025) centre (-197, 16.025) ccw
  line L94 (-197, 16.525) -> (-184, 16.525)
  arc A95 (-183.5, 16.025) -> (-184, 16.525) centre (-184, 16.025) ccw
  line L95 (-183.5, 16.025) -> (-183.5, 3.025)
  arc A96 (-7.7875, 21.575) -> (-7.2875, 22.075) centre (-7.7875, 22.075) ccw
  line L96 (-7.7875, 21.575) -> (-20.7875, 21.575)
  arc A97 (-21.2875, 22.075) -> (-20.7875, 21.575) centre (-20.7875, 22.075) ccw
  line L97 (-21.2875, 22.075) -> (-21.2875, 35.075)
  arc A98 (-20.7875, 35.575) -> (-21.2875, 35.075) centre (-20.7875, 35.075) ccw
  line L98 (-20.7875, 35.575) -> (-7.7875, 35.575)
  arc A99 (-7.2875, 35.075) -> (-7.7875, 35.575) centre (-7.7875, 35.075) ccw
  line L99 (-7.2875, 35.075) -> (-7.2875, 22.075)
  arc A100 (-107.8, 2.525) -> (-107.3, 3.025) centre (-107.8, 3.025) ccw
  line L100 (-107.8, 2.525) -> (-120.8, 2.525)
  arc A101 (-121.3, 3.025) -> (-120.8, 2.525) centre (-120.8, 3.025) ccw
  line L101 (-121.3, 3.025) -> (-121.3, 16.025)
  arc A102 (-120.8, 16.525) -> (-121.3, 16.025) centre (-120.8, 16.025) ccw
  line L102 (-120.8, 16.525) -> (-107.8, 16.525)
  arc A103 (-107.3, 16.025) -> (-107.8, 16.525) centre (-107.8, 16.025) ccw
  line L103 (-107.3, 16.025) -> (-107.3, 3.025)
  arc A104 (-22.075, 2.525) -> (-21.575, 3.025) centre (-22.075, 3.025) ccw
  line L104 (-22.075, 2.525) -> (-35.075, 2.525)
  arc A105 (-35.575, 3.025) -> (-35.075, 2.525) centre (-35.075, 3.025) ccw
  line L105 (-35.575, 3.025) -> (-35.575, 16.025)
  arc A106 (-35.075, 16.525) -> (-35.575, 16.025) centre (-35.075, 16.025) ccw
  line L106 (-35.075, 16.525) -> (-22.075, 16.525)
  arc A107 (-21.575, 16.025) -> (-22.075, 16.525) centre (-22.075, 16.025) ccw
  line L107 (-21.575, 16.025) -> (-21.575, 3.025)
  arc A108 (-79.225, 2.525) -> (-78.725, 3.025) centre (-79.225, 3.025) ccw
  line L108 (-79.225, 2.525) -> (-92.225, 2.525)
  arc A109 (-92.725, 3.025) -> (-92.225, 2.525) centre (-92.225, 3.025) ccw
  line L109 (-92.725, 3.025) -> (-92.725, 16.025)
  arc A110 (-92.225, 16.525) -> (-92.725, 16.025) centre (-92.225, 16.025) ccw
  line L110 (-92.225, 16.525) -> (-79.225, 16.525)
  arc A111 (-78.725, 16.025) -> (-79.225, 16.525) centre (-79.225, 16.025) ccw
  line L111 (-78.725, 16.025) -> (-78.725, 3.025)
  arc A112 (-41.125, 2.525) -> (-40.625, 3.025) centre (-41.125, 3.025) ccw
  line L112 (-41.125, 2.525) -> (-54.125, 2.525)
  arc A113 (-54.625, 3.025) -> (-54.125, 2.525) centre (-54.125, 3.025) ccw
  line L113 (-54.625, 3.025) -> (-54.625, 16.025)
  arc A114 (-54.125, 16.525) -> (-54.625, 16.025) centre (-54.125, 16.025) ccw
  line L114 (-54.125, 16.525) -> (-41.125, 16.525)
  arc A115 (-40.625, 16.025) -> (-41.125, 16.525) centre (-41.125, 16.025) ccw
  line L115 (-40.625, 16.025) -> (-40.625, 3.025)
  arc A116 (-60.175, 2.525) -> (-59.675, 3.025) centre (-60.175, 3.025) ccw
  line L116 (-60.175, 2.525) -> (-73.175, 2.525)
  arc A117 (-73.675, 3.025) -> (-73.175, 2.525) centre (-73.175, 3.025) ccw
  line L117 (-73.675, 3.025) -> (-73.675, 16.025)
  arc A118 (-73.175, 16.525) -> (-73.675, 16.025) centre (-73.175, 16.025) ccw
  line L118 (-73.175, 16.525) -> (-60.175, 16.525)
  arc A119 (-59.675, 16.025) -> (-60.175, 16.525) centre (-60.175, 16.025) ccw
  line L119 (-59.675, 16.025) -> (-59.675, 3.025)
  arc A120 (-3.025, 2.525) -> (-2.525, 3.025) centre (-3.025, 3.025) ccw
  line L120 (-3.025, 2.525) -> (-16.025, 2.525)
  arc A121 (-16.525, 3.025) -> (-16.025, 2.525) centre (-16.025, 3.025) ccw
  line L121 (-16.525, 3.025) -> (-16.525, 16.025)
  arc A122 (-16.025, 16.525) -> (-16.525, 16.025) centre (-16.025, 16.025) ccw
  line L122 (-16.025, 16.525) -> (-3.025, 16.525)
  arc A123 (-2.525, 16.025) -> (-3.025, 16.525) centre (-3.025, 16.025) ccw
  line L123 (-2.525, 16.025) -> (-2.525, 3.025)
  arc A124 (-126.85, 2.525) -> (-126.35, 3.025) centre (-126.85, 3.025) ccw
  line L124 (-126.85, 2.525) -> (-139.85, 2.525)
  arc A125 (-140.35, 3.025) -> (-139.85, 2.525) centre (-139.85, 3.025) ccw
  line L125 (-140.35, 3.025) -> (-140.35, 16.025)
  arc A126 (-139.85, 16.525) -> (-140.35, 16.025) centre (-139.85, 16.025) ccw
  line L126 (-139.85, 16.525) -> (-126.85, 16.525)
  arc A127 (-126.35, 16.025) -> (-126.85, 16.525) centre (-126.85, 16.025) ccw
  line L127 (-126.35, 16.025) -> (-126.35, 3.025)
  line L128 (-204.025, 1.8) -> (-204.225, 1.8)
  arc A128 (-204.225, 1.8) -> (-205.025, 1) centre (-204.225, 1) ccw
  line L129 (-205.025, 1) -> (-205.025, 0.8)
  arc A129 (-205.025, 0.8) -> (-204.225, 0) centre (-204.225, 0.8) ccw
  line L130 (-204.225, 0) -> (4.2, 0)
  arc A130 (4.2, 0) -> (5, 0.8) centre (4.2, 0.8) ccw
  line L131 (5, 0.8) -> (5, 1)
  arc A131 (5, 1) -> (4.2, 1.8) centre (4.2, 1) ccw
  line L132 (4.2, 1.8) -> (4, 1.8)
  arc A132 (4.0006, 4.2) -> (4, 1.8) centre (4, 3) ccw
  line L133 (4.0006, 4.2) -> (4.2, 4.2)
  arc A133 (4.2, 4.2) -> (5, 5) centre (4.2, 5) ccw
  line L134 (5, 5) -> (5, 5.2)
  arc A134 (5, 5.2) -> (4.2, 6) centre (4.2, 5.2) ccw
  line L135 (4.2, 6) -> (0, 6)
  line L136 (0, 6) -> (0, 54.1812)
  line L137 (0, 54.1812) -> (4.2, 54.1812)
  arc A135 (4.2, 54.1812) -> (5, 54.9812) centre (4.2, 54.9812) ccw
  line L138 (5, 54.9812) -> (5, 55.1812)
  arc A136 (5, 55.1812) -> (4.2, 55.9812) centre (4.2, 55.1812) ccw
  line L139 (4.2, 55.9812) -> (4.0098, 55.9812)
  arc A137 (4.012, 58.3812) -> (4.0098, 55.9812) centre (4.0098, 57.1812) ccw
  line L140 (4.012, 58.3812) -> (4.2, 58.3812)
  arc A138 (4.2, 58.3812) -> (5, 59.1812) centre (4.2, 59.1812) ccw
  line L141 (5, 59.1812) -> (5, 59.3812)
  arc A139 (5, 59.3812) -> (4.2, 60.1812) centre (4.2, 59.3812) ccw
  line L142 (4.2, 60.1812) -> (-63.9625, 60.1812)
  line L143 (-63.9625, 60.1812) -> (-63.9625, 71.2)
  arc A140 (-63.9625, 71.2) -> (-68.9625, 76.2) centre (-68.9625, 71.2) ccw
  line L144 (-68.9625, 76.2) -> (-131.0625, 76.2)
  arc A141 (-131.0625, 76.2) -> (-136.0625, 71.2) centre (-131.0625, 71.2) ccw
  line L145 (-136.0625, 71.2) -> (-136.0625, 65.1812)
  arc A142 (-141.0625, 60.1812) -> (-136.0625, 65.1812) centre (-141.0625, 65.1812) ccw
  line L146 (-141.0625, 60.1812) -> (-204.225, 60.1812)
  arc A143 (-204.225, 60.1812) -> (-205.025, 59.3812) centre (-204.225, 59.3812) ccw
  line L147 (-205.025, 59.3812) -> (-205.025, 59.175)
  arc A144 (-205.025, 59.175) -> (-204.225, 58.375) centre (-204.225, 59.175) ccw
  line L148 (-204.225, 58.375) -> (-204.025, 58.375)
  arc A145 (-204.025, 55.975) -> (-204.025, 58.375) centre (-204.025, 57.175) ccw
  line L149 (-204.025, 55.975) -> (-204.225, 55.975)
  arc A146 (-204.225, 55.975) -> (-205.025, 55.175) centre (-204.225, 55.175) ccw
  line L150 (-205.025, 55.175) -> (-205.025, 54.9812)
  arc A147 (-205.025, 54.9812) -> (-204.225, 54.1812) centre (-204.225, 54.9812) ccw
  line L151 (-204.225, 54.1812) -> (-200.025, 54.1812)
  line L152 (-200.025, 54.1812) -> (-200.025, 6)
  line L153 (-200.025, 6) -> (-204.225, 6)
  arc A148 (-204.225, 6) -> (-205.025, 5.2) centre (-204.225, 5.2) ccw
  line L154 (-205.025, 5.2) -> (-205.025, 5)
  arc A149 (-205.025, 5) -> (-204.225, 4.2) centre (-204.225, 5) ccw
  line L155 (-204.225, 4.2) -> (-204.0245, 4.2)
  arc A150 (-204.025, 1.8) -> (-204.0245, 4.2) centre (-204.025, 3) ccw
  line L156 (-102.5375, 18.575) -> (-104.3, 18.575)
  line L157 (-104.3, 18.575) -> (-95.725, 18.575)
  line L158 (-95.725, 18.575) -> (-95.725, 0)
  line L159 (-95.725, 0) -> (-104.3, 0)
  line L160 (-104.3, 0) -> (-104.3, 18.575)
  line L161 (-95.725, 56.675) -> (-104.3, 56.675)
  line L162 (-95.725, 38.575) -> (-104.3, 38.575)
  line L163 (-104.3, 47.625) -> (-104.3, 38.575)
  line L164 (-95.725, 47.625) -> (-95.725, 56.675)
  line L165 (-104.3, 56.675) -> (-104.3, 47.625)
  line L166 (-95.725, 47.625) -> (-95.725, 38.575)
  constraint horizontal L157
  constraint vertical L158
  constraint horizontal L159
  constraint vertical L160
  constraint coincident L130 L158.end
  constraint perpendicular L9 L161
  constraint perpendicular L162 L163
  constraint perpendicular L161 L164
  constraint perpendicular L162 L166
extrude "Extrude2" add sketch "Sketch2" along normal blind 8 contours L130 L156 L157 L158 L159 L160 | L161 L162 L163 L164 L165 L166
chamfer "Chamfer1" distance 0.5 angle 45 2 faces at (98.5833, -6.1917, 9.5) (98.5833, -50.6417, 9.5) tangent chain off
